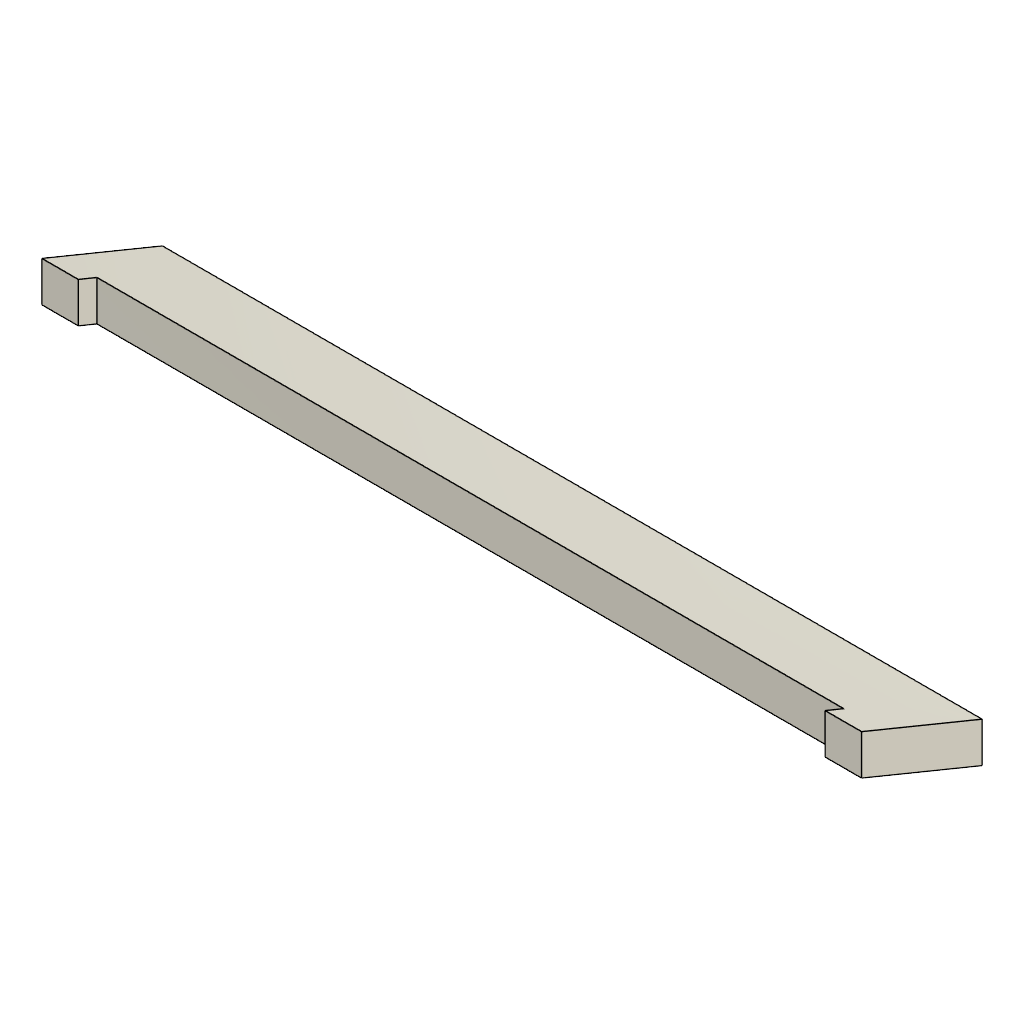
name_sign_LED_holder_top_back (Autodesk Fusion 360 design; units mm, degrees)
part number: 2026-10-25-17-00-14-466
Autodesk Fusion 360 part; units mm, degrees
sketch "Name sign LED holder top" plane through (0, 0, 0) normal (1, 0, 0) x (0, 1, 0)
  line L0 (0, 24.0894) -> (0, 13.281)
  line L1 (0, 13.281) -> (32.3823, 0)
  line L2 (32.3823, 0) -> (32.3823, 10.8084)
  line L3 (32.3823, 10.8084) -> (0, 24.0894)
  dimension "d1" = 35
  dimension "d2" = 10
  dimension "d3" = 112.3
  constraint vertical L0
  constraint parallel L0 L2
  constraint parallel L1 L3
  measures "d1" distance of L0.end L1.end
  measures "d2" distance of L1 L3
  measures "d3" angle of L0 L3
extrude "Extrude1" add sketch "Name sign LED holder top" along normal blind 220
sketch "Magnet holes" plane through (0, 4.6626, 11.3687) normal (0, -0.379456, -0.92521) x (1, 0, 0)
  line L0 (0, 5.0396) -> (0, -29.9604)
  line L1 (0, -29.9604) -> (220, -29.9604)
  line L2 (220, -29.9604) -> (220, 5.0396)
  line L3 (220, 5.0396) -> (0, 5.0396)
  circle A0 centre (10, -7.4604) radius 2.75
  dimension "d19" = 5.5
  dimension "d20" = 12.5
  dimension "d21" = 10
  measures "d19" diameter of A0
  measures "d20" distance of L3 A0.centre
  measures "d21" distance of L0 A0.centre
extrude "Extrude2" cut sketch "Magnet holes" against normal blind 1.5 contours A0
pattern_linear "R-Pattern1" count 4 spacing 66.6667 along (1, 0, 0) count 2 spacing 15 along (0, 0.92521, -0.379456) of "Extrude2"
sketch "Supports" plane through (220, 0, 0) normal (1, 0, 0) x (0, 1, 0)
  line L0 (32.3823, 10.8084) -> (0, 24.0894)
  line L1 (0, 24.0894) -> (0, 13.281)
  line L2 (0, 13.281) -> (32.3823, 0)
  line L3 (32.3823, 0) -> (32.3823, 10.8084)
  line L4 (5, 22.0387) -> (5, 11.2304)
  line L5 (5, 22.0387) -> (0, 24.0894)
  line L6 (0, 24.0894) -> (0, 13.281)
  line L7 (0, 13.281) -> (5, 11.2304)
  dimension "d28" = 5
  constraint coincident L0 L4.start
  constraint coincident L2 L4.end
  constraint parallel L1 L4
  constraint coincident L0.end L1.start
  constraint coincident L1.end L2.start
  measures "d28" distance of L1 L4
extrude "Extrude3" cut sketch "Supports" against normal blind 200.4 from surface at -9.8 contours L0 L1 L2 L4 L5 L6 L7
equation "magnet_hole_diameter = 5.5 mm"
equation "magnet_hole_depth = 1.5 mm"
equation "number_of_magnet_columns = 4"
equation "number_of_magnet_rows = 2"
equation "magnet_hole_side_offset = 10 mm"
equation "magnet_hole_top_offset = 7.5 mm"
equation "magnet_pattern_length = 220.00 mm - 2 * ( magnet_hole_side_offset )"
equation "magnet_pattern_height = 35.00 mm - vertical_part_width - 2 * ( magnet_hole_top_offset )"
equation "vertical_part_width = 5.00 mm"
equation "support_width = 10 mm"
equation "support_clearance = 0.2 mm"
equation "d19 = magnet_hole_diameter"
equation "d20 = vertical_part_width + magnet_hole_top_offset"
equation "d21 = magnet_hole_side_offset"
equation "d22 = -magnet_hole_depth"
equation "d24 = number_of_magnet_columns"
equation "d25 = number_of_magnet_rows"
equation "d26 = magnet_pattern_length"
equation "d27 = magnet_pattern_height"
equation "d29 = -( support_width - support_clearance )"
equation "d30 = -( 220.00 mm - 2 * support_width + 2 * support_clearance )"
named bodies: "Name sign LED holder top"
